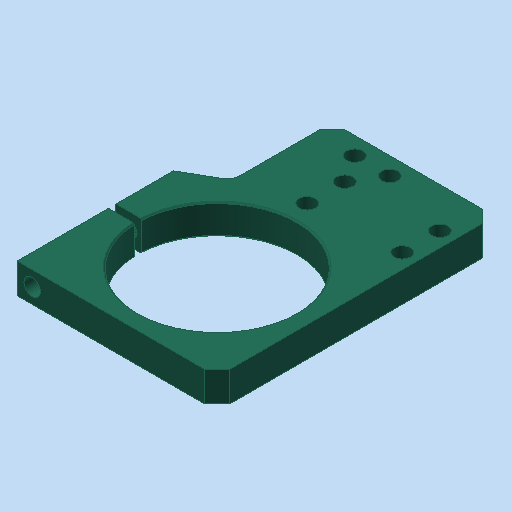
# Autodesk Inventor part: MM0868AN100_G80_112
Saved by Autodesk Inventor 2023.3 (Build 273359000, 359)
## iProperties
RuleStatus: InUse
Created: 2021-07-06
Part Number: MM0868AN100_G80_112
Material: 3.3547 AlMg4,5Mn0,7 - AW 5083
Description: =<RBPARTNOTITLE2>
Document SubType Name: Modeling
Designer: Rose
Mass: 150.583 g
Surface Area: 189.125 cm^2
Volume: 55.7713 cm^3
Density: 2.7 g/cm^3
Appearance: Jadegr-D
AnP_Kategorie: 1
AnP_Material: =<Material>
AnP_TemplVers: 20200821
RBDOCUMENTTYPE: DRF
RBDOCUMENTVERSION: 00
RBDRAWINGMAINSCALE: 1:1
RBDRAWINGMISSINGSPEC: --
RBDRAWINGVOLUME: --
RBDSV1: 0850
RBGBEDGESIN1: +0,5
RBGBEDGESIN2: +0,2
RBGBEDGESOUT1: -0,3
RBGBEDGESOUT2: -0,1
RBMATERIAL: =<Material>
RBMATMEETS: --
RBMATNO: =<Part Number>
RBPARTMADEOF: Fl.80x12x114
RBPARTNO: SIEHE MNR
RBPARTNOTITLE1: manufactured part
RBPARTNOTITLE2: Anfertigungsteil
RBPARTSAFETYINDICATOR: --
RBSURFACE: anodised colourless
RBSURFACE2: eloxiert farblos
RBZEDGESNORM: ISO13715:2002-06
RBZGENDIMCLASS: m
RBZGENDIMNORM: ISO 2768-1:1989-11
RBZGENGEOCLASS: H
RBZGENGEONORM: ISO 2768-2:1989-11
RBZSURFACENORM: ISO13D2:2002-02
RBZTOLERANCENORM: ISO 14405-1:2010-12
Author: Rose
Keywords: =<RBPARTMADEOF>
Comments: =<RBSURFACE2>
Revision Number: 01
Autodesk Inventor part; units mm, degrees
ref_plane "YZ Plane" through (0, 0, 0) normal (1, 0, 0) x (0, 1, 0)
ref_plane "XZ Plane" through (0, 0, 0) normal (0, 1, 0) x (-1, 0, 0)
ref_plane "XY Plane" through (0, 0, 0) normal (0, 0, 1) x (1, 0, 0)
sketch "Skizze1" plane through (0, 0, 0) normal (0, 0, 1) x (1, 0, 0)
  line L0 (0, 95.2) -> (0, -60.2) projected
  line L1 (-58, 0) -> (54, 0) projected
  line L2 (-27, 73) -> (38, 73)
  line L3 (38, 73) -> (38, -38)
  line L4 (38, -38) -> (-42, -38)
  line L5 (-42, -38) -> (-42, 24.453)
  line L6 (-27, 73) -> (-27, 36)
  line L7 (-29.5, 31.6699) -> (-42, 24.453)
  arc A0 (-29.5, 31.6699) -> (-27, 36) centre (-32, 36) ccw
  dimension "d0" = 38
  dimension "d1" = 80
  dimension "d2" = 38
  dimension "d3" = 73
  dimension "d52" = 5
  dimension "d54" = 27
  dimension "d58" = 37
  dimension "d59" = 60
  constraints: 12 end point, 2 parallel, 2 point on circle, 2 tangent, 1 centre point, 1 horizontal, 1 perpendicular, 1 vertical
  measures "d0" distance between parallel lines of L0 L3
  measures "d1" distance between parallel lines of L3 L5
  measures "d2" distance between parallel lines of L4 L1
  measures "d3" distance between parallel lines of L1 L2
  measures "d52" radius of A0
  measures "d54" distance between parallel lines of L6 L0
  measures "d58" distance from line of A0.centre L2
  measures "d59" angle of L5 L7
extrude "Extrusion1" add sketch "Skizze1" along normal blind 12
sketch "Skizze2" plane through (0, 0, 12) normal (0, 0, 1) x (1, 0, 0)
  line L0 (0, 95.2) -> (0, -60.2) projected
  line L1 (-58, 0) -> (54, 0) projected
  point P0 (0, 0)
  constraints: 2 point on line
hole "Bohrung1" at (0, 0, 12) direction (0, 0, -1) diameter 63.4 end through all
sketch "Skizze3" plane through (0, 0, 0) normal (0, 0, -1) x (-1, 0, 0)
  line L0 (0, -60.2) -> (0, 95.2) projected
  line L1 (-32, 42) -> (-32, 57)
  line L2 (-3, 66) -> (11, 66)
  line L3 (4, 40) -> (4, 55)
  line L4 (-38, -38) -> (-38, 73) projected
  line L5 (-38, 73) -> (27, 73) projected
  point P0 (4, 66)
  dimension "d13" = 15
  dimension "d17" = 29
  dimension "d18" = 14
  dimension "d51" = 6
  dimension "d55" = 7
  dimension "d56" = 9
  dimension "d57" = 11
  constraints: 6 end point, 5 coincident, 2 vertical, 1 horizontal, 1 midpoint, 1 parallel, 1 vertical alignment
  measures "d13" distance of L1.start L1.end
  measures "d17" horizontal distance of point (-3, 66) point (-32, 57)
  measures "d18" distance of point (11, 66) point (-3, 66)
  measures "d51" distance from line of L4 point (-32, 57)
  measures "d55" distance from line of L5 point (11, 66)
  measures "d56" vertical distance of point (-32, 57) point (-3, 66)
  measures "d57" vertical distance of point (11, 66) point (4, 55)
hole "Bohrung2" at (-11, 66, 0) at (3, 66, 0) at (32, 57, 0) at (32, 42, 0) at (-4, 40, 0) at (-4, 55, 0) direction (0, 0, 1) diameter 6.6 end through all
sketch "Skizze4" plane through (0, 0, 0) normal (0, 0, -1) x (-1, 0, 0)
  line L0 (42, 24.453) -> (42, -38) projected
  circle A0 centre (0, 0) radius 31.7 projected
  line L1 (42, 1.5) -> (0, 1.5)
  line L2 (0, 1.5) -> (0, -1.5)
  line L3 (0, -1.5) -> (42, -1.5)
  line L4 (42, -1.5) -> (42, 1.5)
  point P0 (42, -1.5)
  dimension "d26" = 3
  constraints: 8 end point, 2 parallel, 1 coincident, 1 horizontal, 1 midpoint, 1 perpendicular, 1 point on line
  measures "d26" distance between parallel lines of L1 L3
extrude "Extrusion2" cut sketch "Skizze4" against normal through all contours L0 L3 A0 L1 | A0 L3 L2 L1 picked at (10.5667, 0)
sketch "Skizze5" plane through (-42, -38, 0) normal (0, -1, 0) x (1, 0, 0)
  line L0 (0, 0) -> (0, 12) projected
  point P0 (6, 6)
  point P1 (0, 6)
  dimension "d29" = 6
  constraints: 1 horizontal alignment, 1 midpoint
  measures "d29" distance from line of L0 point (6, 6)
hole "Bohrung3" at (-36, -38, 6) direction (0, 1, 0) diameter 6.6 depth 36.5
sketch "Skizze6" plane through (-42, 1.5, 0) normal (0, -1, 0) x (1, 0, 0)
  circle A0 centre (6, 6) radius 3.3 projected
  point P0 (6, 6)
  constraints: 1 coincident
hole "Bohrung4" at (-36, 1.5, 6) direction (0, 1, 0) diameter 4.917 depth 20 thread size "M6x1" designation "M6" class "6H" standard "ISO Metric profile"
chamfer "Fase1" distance 0.5 angle 45 4 edges at (-21.8785, -22.9395, 12) (22.9395, 21.8785, 12) (-21.8785, -22.9395, 0) (22.9395, 21.8785, 0)
chamfer "Fase2" distance 5 angle 45 3 edges at (38, -38, 6) (38, 73, 6) (-27, 73, 6)
